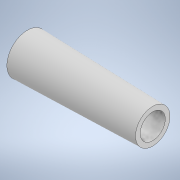
# Autodesk Inventor part: teaca gresita
Saved by Autodesk Inventor 2022.6 (Build 266554000, 554)
## iProperties
Created: 2026-03-16
Part Number: teaca gresita
Material: Generic
Document SubType Name: Modeling
Designer: Dragos Macovei
Density: 1 g/cm^3
Appearance: Default
Author: Dragos Macovei
Autodesk Inventor part; units mm, degrees
ref_plane "YZ Plane" through (0, 0, 0) normal (1, 0, 0) x (0, 1, 0)
ref_plane "XZ Plane" through (0, 0, 0) normal (0, 1, 0) x (-1, 0, 0)
ref_plane "XY Plane" through (0, 0, 0) normal (0, 0, 1) x (1, 0, 0)
sketch "Sketch1" plane through (0, 0, 0) normal (0, 1, 0) x (-1, 0, 0)
  line L0 (40, 0) -> (40, -5)
  line L1 (40, -5) -> (40, -6.5)
  line L2 (0, 0) -> (40, 0)
  line L3 (0, 0) -> (0, -4)
  line L4 (0, -4) -> (0, -5.5)
  line L5 (0, -5.5) -> (40, -6.5)
  line L6 (40, -5) -> (0, -4)
  dimension "d0" = 5
  dimension "d1" = 1.5
  dimension "d2" = 40
  dimension "d3" = 4
  dimension "d4" = 1.5
  constraints: 14 end point, 2 point on line, 2 vertical, 1 horizontal
  measures "d0" distance of L0.start L0.end
  measures "d1" distance of L0.end L1.end
  measures "d2" distance of L2.start L0.start
  measures "d3" distance of L2.start L3.end
  measures "d4" distance of L3.end L4.end
revolve "Revolution1" add sketch "Sketch1" angle 360 about axis through (0, 0, 0) along (-1, 0, 0) contours L1 L5 L4 L6
body "Solid1"
